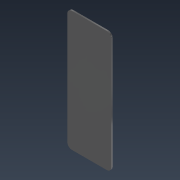
# Autodesk Inventor part: SP24V1 Goma Pedales
Saved by Autodesk Inventor 2021.2 (Build 252289000, 289)
## iProperties
Created: 2026-10-13
Part Number: SP24V1 Goma Pedales
Material: Rubber
Document SubType Name: Modeling
Designer: nelso
Density: 0.93 g/cm^3
Appearance: Rubber - Black - Version 1.1
Author: nelso
Autodesk Inventor part; units mm, degrees
ref_plane "YZ Plane" through (0, 0, 0) normal (1, 0, 0) x (0, 1, 0)
ref_plane "XZ Plane" through (0, 0, 0) normal (0, 1, 0) x (-1, 0, 0)
ref_plane "XY Plane" through (0, 0, 0) normal (0, 0, 1) x (1, 0, 0)
sketch "Sketch1" plane through (0, 0, 0) normal (0, 1, 0) x (-1, 0, 0)
  line L0 (30, 82.5) -> (-30, 82.5)
  line L1 (-30, 82.5) -> (-30, -82.5)
  line L2 (-30, -82.5) -> (30, -82.5)
  line L3 (30, -82.5) -> (30, 82.5)
  line L4 (30, 82.5) -> (-30, -82.5) construction
  line L5 (-30, 82.5) -> (30, -82.5) construction
  point P0 (0, 0)
  dimension "d0" = 60
  dimension "d1" = 165
  constraints: 12 end point, 2 midpoint, 2 parallel, 1 horizontal, 1 perpendicular
  measures "d0" distance of L2.end L1.end
  measures "d1" distance of L1.end L0.end
extrude "Extrusion1" add sketch "Sketch1" along normal blind 2
fillet "Fillet1" radius 6 4 edges at (30, 1, 82.5) (-30, 1, 82.5) (-30, 1, -82.5) (30, 1, -82.5)
body "Solid1"
